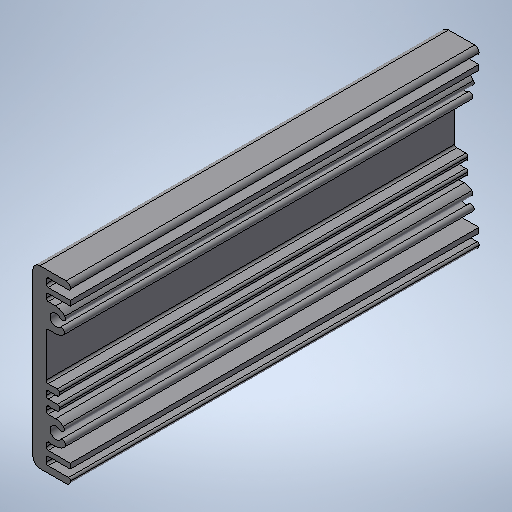
# Autodesk Inventor part: 3dext
Saved by Autodesk Inventor 2025.3 (Build 293356000, 356)
## iProperties
RuleStatus: InUse
Created: 2026-11-10
Part Number: 3dext
Project: COMMON
Material: Generic
Catalog Web Link: https://www.janelia.org/
Vendor: HHMI: JRC - JET
Document SubType Name: Modeling
Designer: sawtelles
Density: 1 g/cm^3
Appearance: Default
AfterDocSave0: file://Part Number Cleaner
LAB/DEPT: COMMON
REQUESTING SCIENTIST: COMMON
DESIGN DEPARTMENT: HHMI: JRC - ID&F
ALTERED ITEM PART NUMBER: N/A
ALTERED ITEM VENDOR: N/A
ALTERED ITEM DESCRIPTION: N/A
Title: Standard
Author: sawtelles
Revision Number: 0
Autodesk Inventor part; units mm, degrees
ref_plane "YZ Plane" through (0, 0, 0) normal (1, 0, 0) x (0, 1, 0)
ref_plane "XZ Plane" through (0, 0, 0) normal (0, 1, 0) x (-1, 0, 0)
ref_plane "XY Plane" through (0, 0, 0) normal (0, 0, 1) x (1, 0, 0)
sketch "Sketch1" plane through (0, 0, 0) normal (0, 0, 1) x (1, 0, 0)
  point P0 (0, 0)
sketch "Sketch2" plane through (0, 0, 0) normal (0, 0, 1) x (1, 0, 0)
  arc A0 (3.0167, -28.0478) -> (3.1977, -29.8318) centre (1.9442, -29.0578) ccw
  arc A1 (3.0167, -28.0478) -> (3.7847, -26.7536) centre (3.2974, -27.3394) ccw
  arc A2 (3.7847, -26.7536) -> (1.8682, -26.0606) centre (1.868, -29.0578) ccw
  line L0 (1.8682, -26.0606) -> (0, -26.0605)
  arc A3 (-0.508, -25.5525) -> (0, -26.0605) centre (0, -25.5525) ccw
  line L1 (-0.508, -25.5525) -> (-0.508, -24.7905)
  arc A4 (0, -24.2825) -> (-0.508, -24.7905) centre (0, -24.7905) ccw
  line L2 (0, -24.2825) -> (2.286, -24.2825)
  arc A5 (2.286, -24.2825) -> (2.794, -23.7745) centre (2.286, -23.7745) ccw
  line L3 (2.794, -23.7745) -> (2.794, -23.2665)
  arc A6 (2.794, -23.2665) -> (2.286, -22.7585) centre (2.286, -23.2665) ccw
  line L4 (2.286, -22.7585) -> (0, -22.7585)
  arc A7 (-0.508, -22.2505) -> (0, -22.7585) centre (0, -22.2505) ccw
  line L5 (-0.508, -22.2505) -> (-0.508, -21.4885)
  arc A8 (0, -20.9805) -> (-0.508, -21.4885) centre (0, -21.4885) ccw
  line L6 (0, -20.9805) -> (2.286, -20.9805)
  arc A9 (2.286, -20.9805) -> (2.794, -20.4725) centre (2.286, -20.4725) ccw
  line L7 (2.794, -20.4725) -> (2.794, -19.9645)
  arc A10 (2.794, -19.9645) -> (2.286, -19.4565) centre (2.286, -19.9645) ccw
  line L8 (2.286, -19.4565) -> (0, -19.4565)
  arc A11 (-0.508, -18.9485) -> (0, -19.4565) centre (0, -18.9485) ccw
  line L9 (-0.508, -18.9485) -> (-0.508, -18.1865)
  line L10 (-0.508, -9.0425) -> (-0.508, -8.2805)
  arc A12 (0, -7.7725) -> (-0.508, -8.2805) centre (0, -8.2805) ccw
  line L11 (0, -7.7725) -> (1.8682, -7.7724)
  arc A13 (1.8682, -7.7724) -> (3.7847, -7.0794) centre (1.868, -4.7752) ccw
  arc A14 (3.7847, -7.0794) -> (3.0167, -5.7852) centre (3.2974, -6.4936) ccw
  arc A15 (3.1977, -4.0012) -> (3.0167, -5.7852) centre (1.9442, -4.7752) ccw
  arc A16 (3.1977, -4.0012) -> (4.1723, -2.8585) centre (3.5865, -3.3458) ccw
  arc A17 (4.1723, -2.8585) -> (1.868, -1.778) centre (1.868, -4.7752) ccw
  line L12 (1.868, -1.778) -> (0, -1.778)
  arc A18 (-0.508, -1.27) -> (0, -1.778) centre (0, -1.27) ccw
  line L13 (-0.508, -1.27) -> (-0.508, -0.508)
  arc A19 (0, 0) -> (-0.508, -0.508) centre (0, -0.508) ccw
  line L14 (0, 0) -> (5.5121, 0)
  line L15 (5.5121, 1.2572) -> (0, 1.2572)
  arc A20 (-0.508, 1.7652) -> (0, 1.2572) centre (0, 1.7652) ccw
  line L16 (-0.508, 1.7652) -> (-0.508, 2.7812)
  arc A21 (0, 3.2892) -> (-0.508, 2.7812) centre (0, 2.7812) ccw
  line L17 (0, 3.2892) -> (5.08, 3.2892)
  arc A22 (5.08, 3.2892) -> (5.588, 3.7972) centre (5.08, 3.7972) ccw
  arc A23 (5.588, 3.7972) -> (4.4704, 4.9148) centre (4.4704, 3.7972) ccw
  line L18 (4.4704, 4.9148) -> (-2.032, 4.9148)
  arc A24 (-2.032, 4.9148) -> (-3.81, 3.1368) centre (-2.032, 3.1368) ccw
  line L19 (-3.81, 3.1368) -> (-3.81, 1.2794)
  line L20 (-3.81, -35.1174) -> (-3.81, -36.9698)
  arc A25 (-3.81, -36.9698) -> (-2.032, -38.7478) centre (-2.032, -36.9698) ccw
  line L21 (-2.032, -38.7478) -> (4.4704, -38.7478)
  arc A26 (4.4704, -38.7478) -> (5.588, -37.6302) centre (4.4704, -37.6302) ccw
  arc A27 (5.588, -37.6302) -> (5.08, -37.1272) centre (5.08, -37.6352) ccw
  line L22 (5.08, -37.1272) -> (0, -37.1272)
  arc A28 (-0.508, -36.6192) -> (0, -37.1272) centre (0, -36.6192) ccw
  line L23 (-0.508, -36.6192) -> (-0.508, -35.6032)
  arc A29 (0, -35.0952) -> (-0.508, -35.6032) centre (0, -35.6032) ccw
  line L24 (0, -35.0952) -> (5.5121, -35.0952)
  line L25 (5.5121, -33.833) -> (0, -33.833)
  arc A30 (-0.508, -33.325) -> (0, -33.833) centre (0, -33.325) ccw
  line L26 (-0.508, -33.325) -> (-0.508, -32.563)
  arc A31 (0, -32.055) -> (-0.508, -32.563) centre (0, -32.563) ccw
  line L27 (0, -32.055) -> (1.868, -32.055)
  arc A32 (1.868, -32.055) -> (4.1723, -30.9745) centre (1.868, -29.0578) ccw
  arc A33 (4.1723, -30.9745) -> (3.1977, -29.8318) centre (3.5865, -30.4872) ccw
  arc A34 (-3.81, 1.2794) -> (-3.8097, 1.2572) centre (-3.048, 1.2794) ccw
  arc A35 (-3.8097, -35.0952) -> (-3.81, -35.1174) centre (-3.048, -35.1174) ccw
  line L28 (-3.8097, 1.2572) -> (-3.8097, -35.0952)
  line L29 (5.5121, 1.2572) -> (5.5121, 0)
  line L30 (-0.508, -9.0425) -> (-0.508, -18.1865)
  line L31 (5.5121, -33.833) -> (5.5121, -35.0952)
  point P0 (0, 0)
  constraints: 72 point on circle, 64 end point, 36 centre point, 2 perpendicular, 2 point on line, 2 vertical, 1 coincident
extrude "Extrusion1" add sketch "Sketch2" along normal blind 101.6
body "Solid1"
